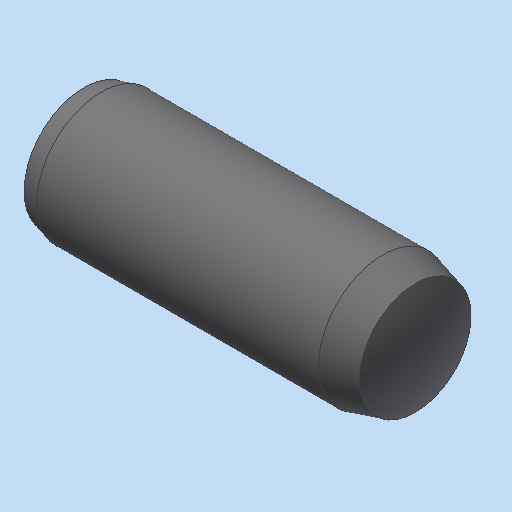
# Autodesk Inventor part: Zylinderstift_DIN_7979D_6_x_16
Saved by Autodesk Inventor 2023.3 (Build 273359000, 359)
## iProperties
Shininess: 64.0
Length Units: 11269
Angle Units: 11279
Time Units: 11290
Mass Units: 11283
Length Display Precision: 3
Angle Display Precision: 2
Compacted: True
Part Number: Zylinderstift_DIN_7979D_6_x_16
Document SubType Name: Modeling
Created: 2004-04-23
Description: =<RBPARTNOTITLE2>
Vendor: NORM8
Designer: C.Fischer
Manufacturer: Standard
Standards Organization: Custom
Density: 7.85 g/cm^3
Material: xStahl_AnP_Dummymaterial
Appearance: Stahl - normal AnP
Mass: 2.67588 g
Surface Area: 4.39505 cm^2
Volume: 0.340877 cm^3
Density: 0.0
Volumn: 0.0
Area: 0.0
PropertySet Name: Model Information
Control State: 0
Master: False
Checked Out: False
CNS_NB: Zylinderstift DIN 7979D 6 x 16
CNS_NN: DIN 7979-D
CNS_NT: Zylinderstift, mit Innengewinde, gehaertet
CNS_NBSYN: Zylinderstift DIN 7979D $NENN.
CNS_LINA: Zylinderstift DIN 7979D 6 x 16
CNS_NENN: 6 x 16
CNS_D: 6.000
CNS_D1: 4.000
CNS_D2: 3.242
CNS_DA: 4.300
CNS_P: 0.700
CNS_L: 16.000
CNS_B: 6.000
CNS_T1: 1.000
CNS_T2: 10.000
CNS_A1: 0.600
CNS_A2: 0.800
CNS_F: 2.100
CNS_KT: X
PSOL_IDENT_0: {C:\partsolutions\data\23d-libs\bosch_bamberg\stifte\scherstifte\din_7979_d.prj},168 {M=Nenngewinde}
PSOL_IDENT_1: ,{VTYP=3D},{NB=Zylinderstift DIN 7979D 6 x 16},{NN=DIN 7979-D},{DATE=26.11.2003},{GEOMDATE=26.11.200
PSOL_IDENT_2: 3},{VERSION=v1},{LINEID=10},{LINESUBID=-1},{WBVAR=}  {NB=Zylinderstift DIN 7979D 6 x 16},{LINA=Zylin
PSOL_IDENT_3: derstift DIN 7979D 6 x 16},{KT=X},{IDNR=},{NENN=6 x 16},{D=6.000},{D1=4.000},{D2=3.242},{DA=4.300},{
PSOL_IDENT_4: P=0.700},{L=16.000},{B=6.000},{T1=1.000},{T2=10.000},{A1=0.600},{A2=0.800},{F=2.100}
RBDRAWINGMISSINGSPEC: --
RBPARTNOTITLE2: Zylinderstift mit Innengewinde, gehaertet
RBPARTNOTITLE1: Parallel pins with internal thread, hardened
AnP_Kategorie: 4
RBPARTMADEOF: DIN 7979 D - 6 x 16
Title: Zylinderstift DIN 7979D 6 x 16
Author: C.Fischer
Keywords: =<RBPARTMADEOF>
Comments: =<RBSURFACE2>
Revision Number: 01
Autodesk Inventor part; units mm, degrees
sketch "Skizze_4" plane through (0, 0, 0) normal (0, 1, 0) x (-1, 0, 0)
  line L0 (-16, 0) -> (0, 0)
  line L1 (-10.9359, 0) -> (-10, -1.621)
  line L2 (-10, -1.621) -> (-1.9163, -1.621)
  line L3 (-1.9163, -1.621) -> (-1, -2.15)
  line L4 (-1, -2.15) -> (0, -2.15)
  line L5 (0, -2.15) -> (0, -2.7856)
  line L6 (0, -2.7856) -> (-0.8, -3)
  line L7 (-0.8, -3) -> (-13.9, -3)
  line L8 (-13.9, -3) -> (-15.4083, -2.5981)
  arc A0 (-16, 0) -> (-15.4083, -2.5981) centre (-10, 0) ccw
  line L9 (-16, 0) -> (-10.9359, 0)
  constraints: 20 end point, 2 point on circle, 1 centre point
revolve "Revolution1" add sketch "Skizze_4" angle 360 about axis through (16, 0, 0) along (1, 0, 0)
thread "Thread1" size "M4x0.7" class "6H" standard "ANSI Metric M Profile" length 8.0837
ref_plane "IP2_XY" through (0, 0, 0) normal (1, 0, 0) x (0, 0, -1)
ref_plane "IP2_YZ" through (0, 0, 0) normal (0, 0, -1) x (0, 1, 0)
ref_plane "IP1_XY" through (8, 0, 0) normal (1, 0, 0) x (0, 0, -1)
ref_plane "IP1_YZ" through (8, 0, 0) normal (0, 0, -1) x (0, 1, 0)
ref_plane "IP3_XY" through (16, 0, 0) normal (1, 0, 0) x (0, 0, -1)
ref_plane "IP3_YZ" through (16, 0, 0) normal (0, 0, -1) x (0, 1, 0)
